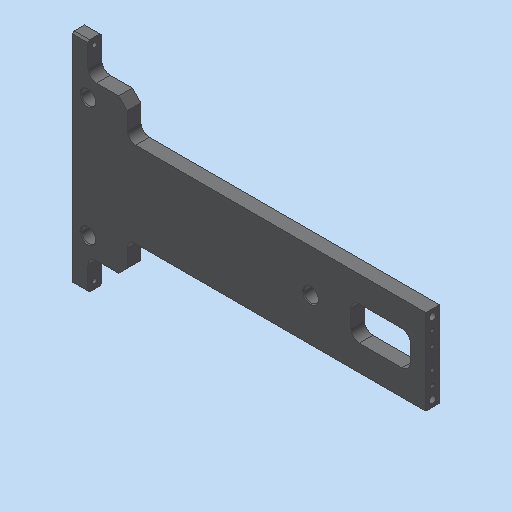
# Autodesk Inventor part: MM0861AN100_G01_120
Saved by Autodesk Inventor 2023.3 (Build 273359000, 359)
## iProperties
Created: 2018-10-29
Part Number: MM0861AN100_G01_120
Material: 1.2842 90MnCrV8
Document SubType Name: Modeling
Designer: Rose
Density: 7.85 g/cm^3
Appearance: Stahl - normal AnP
Mass: 675.833 g
Surface Area: 307.227 cm^2
Volume: 86.0934 cm^3
Description: =<RBPARTNOTITLE2>
RBMATERIAL: =<Material>
RBMATNO: =<Part Number>
RBPARTMADEOF: 150x8x210
RBPARTNOTITLE1: manufactured part
RBPARTNOTITLE2: Anfertigungsteil
MaxAbmaße: 0 x 0 x 0 (FM)
AnP_Material_aktuell: =<Material>
AnP_Kommentar_aktuell: =<Comments>
RBDRAWINGMISSINGSPEC: --
AnP_Kategorie: 1
AnP_Material: =<Material>
RBSURFACE2: HRC 58±2 cehm. vernickelt
Author: Rose
Keywords: =<RBPARTMADEOF>
Comments: =<RBSURFACE2>
Revision Number: 01
Autodesk Inventor part; units mm, degrees
ref_plane "YZ Plane" through (0, 0, 0) normal (1, 0, 0) x (0, 1, 0)
ref_plane "XZ Plane" through (0, 0, 0) normal (0, 1, 0) x (-1, 0, 0)
ref_plane "XY Plane" through (0, 0, 0) normal (0, 0, 1) x (1, 0, 0)
sketch "Skizze1" plane through (0, 0, 0) normal (0, 0, 1) x (1, 0, 0)
  line L0 (0, 9.6) -> (0, -1.6) projected
  line L1 (-41.4, 0) -> (248.4, 0) projected
  line L2 (0, 0) -> (207, 0)
  line L3 (207, 0) -> (207, 8)
  line L4 (207, 8) -> (0, 8)
  line L5 (0, 0) -> (0, 8)
  dimension "d0" = 8
  dimension "d1" = 0
  dimension "d4" = 207
  constraints: 8 end point, 2 perpendicular, 1 collinear, 1 point on line
  measures "d0" distance between parallel lines of L2 L4
  measures "d1" distance between parallel lines of L5 L0
  measures "d4" distance between parallel lines of L3 L0
extrude "Extrusion1" add sketch "Skizze1" along normal mid plane 128
sketch "Skizze2" plane through (0, 0, 64) normal (0, -1, 0) x (1, 0, 0)
  line L0 (0, 25.6) -> (0, -153.6) projected
  line L1 (-41.4, -64) -> (248.4, -64) projected
  point P0 (9, -29)
  point P1 (9, -99)
  point P2 (139.5, -64)
  dimension "d9" = 70
  dimension "d56" = 9
  dimension "d60" = 139.5
  constraints: 1 point on line, 1 symmetric about line
  measures "d9" distance of point (9, -99) point (9, -29)
  measures "d56" distance from line of point (9, -29) L0
  measures "d60" distance from line of point (139.5, -64) L0
hole "Bohrung1" at (9, 0, 35) at (9, 0, -35) at (139.5, 0, 0) direction (0, 1, 0) diameter 8.4 end through all
sketch "Skizze3" plane through (0, 8, 64) normal (0, 1, 0) x (1, 0, 0)
  line L0 (207, 0) -> (207, 128) projected
  line L1 (248.4, 64) -> (-41.4, 64) projected
  line L2 (9, 128) -> (9, 114)
  line L3 (14, 109) -> (32, 109)
  line L4 (9, 0) -> (9, 14)
  line L5 (14, 19) -> (32, 19)
  arc A0 (9, 114) -> (14, 109) centre (14, 114) ccw
  arc A1 (14, 19) -> (9, 14) centre (14, 14) ccw
  line L6 (168, 74) -> (193, 74)
  line L7 (193, 54) -> (168, 54)
  line L8 (163, 59) -> (163, 69)
  arc A2 (168, 74) -> (163, 69) centre (168, 69) ccw
  arc A3 (163, 59) -> (168, 54) centre (168, 59) ccw
  line L9 (0, 0) -> (0, 128) projected
  line L10 (0, 128) -> (207, 128) projected
  line L11 (207, 0) -> (0, 0) projected
  line L12 (37, 89) -> (207, 89)
  line L13 (37, 39) -> (207, 39)
  line L14 (32, 109) -> (32, 94)
  line L15 (32, 34) -> (32, 19)
  arc A4 (32, 94) -> (37, 89) centre (37, 94) ccw
  arc A5 (37, 39) -> (32, 34) centre (37, 34) ccw
  line L16 (198, 69) -> (198, 59)
  arc A6 (198, 69) -> (193, 74) centre (193, 69) ccw
  arc A7 (193, 54) -> (198, 59) centre (193, 59) ccw
  dimension "d22" = 5
  dimension "d23" = 90
  dimension "d25" = 5
  dimension "d28" = 20
  dimension "d52" = 50
  dimension "d53" = 44
  dimension "d54" = 9
  dimension "d55" = 32
  dimension "d61" = 9
  constraints: 24 end point, 16 point on circle, 16 tangent, 9 perpendicular, 8 centre point, 6 equal radius, 4 point on line, 1 collinear, 1 horizontal, 1 parallel, 1 symmetric about line, 2 other
  measures "d22" radius of A0
  measures "d23" distance between parallel lines of L5 L3
  measures "d25" radius of A2
  measures "d28" distance between parallel lines of L7 L6
  measures "d52" distance between parallel lines of L13 L12
  measures "d53" distance between parallel lines of L0 L8
  measures "d54" distance between parallel lines of L2 L9
  measures "d55" distance between parallel lines of L14 L9
  measures "d61" distance between parallel lines of L0 L16
extrude "Extrusion2" cut sketch "Skizze3" against normal through all contours L11 L4 A1 L5 L15 A5 L13 L0 | L12 A4 L14 L3 A0 L2 L10 L0 | L16 A7 L7 A3 L8 L1 | L1 L8 A2 L6 A6 L16
sketch "Skizze4" plane through (14, 8, 45) normal (0, 1, 0) x (1, 0, 0)
  line L0 (-14, 134.6) -> (-14, -44.6) projected
  line L1 (234.4, 45) -> (-55.4, 45) projected
  line L2 (149, 40) -> (149, 50) projected
  point P0 (8, 80)
  point P1 (8, 10)
  point P2 (140.5, 45)
  dimension "d38" = 22
  dimension "d39" = 70
  dimension "d97" = 8.5
  constraints: 1 point on line, 1 symmetric about line
  measures "d38" distance from line of L0 point (8, 80)
  measures "d39" distance of point (8, 10) point (8, 80)
  measures "d97" distance from line of point (140.5, 45) L2
hole "Bohrung2" at (22, 8, -35) at (22, 8, 35) at (154.5, 8, 0) direction (0, -1, 0) diameter 11.7 depth 6
sketch "Skizze5" plane through (0, 0, 64) normal (-1, 0, 0) x (0, 0, 1)
  line L0 (-153.6, 0) -> (25.6, 0) projected
  line L1 (-64, 9.6) -> (-64, -1.6) projected
  line L2 (-124, 4) -> (-4, 4)
  point P0 (-45, 4)
  point P1 (-83, 4)
  point P2 (-106, 4)
  point P3 (-22, 4)
  point P4 (-64, 4)
  dimension "d62" = 4
  dimension "d63" = 120
  dimension "d80" = 38
  dimension "d98" = 84
  constraints: 3 point on line, 3 symmetric about line, 2 end point, 1 coincident, 1 midpoint, 1 parallel
  measures "d62" distance from line of L0 L2.start
  measures "d63" distance of point (-4, 4) L2.start
  measures "d80" distance of point (-83, 4) point (-45, 4)
  measures "d98" distance of point (-22, 4) point (-106, 4)
hole "Bohrung3" at (0, 4, -60) at (0, 4, 60) at (0, 4, 19) at (0, 4, -19) at (0, 4, -42) at (0, 4, 0) at (0, 4, 42) direction (1, 0, 0) diameter 2.459 depth 11 tip angle 118 thread size "M3x0.5" designation "M3" class "6H" standard "ISO Metric profile"
sketch "Skizze6" plane through (207, 0, -25) normal (1, 0, 0) x (0, 0, -1)
  line L0 (-114.6, 0) -> (64.6, 0) projected
  line L1 (-25, -1.6) -> (-25, 9.6) projected
  line L2 (-11, 4) -> (-19, 4)
  point P0 (-39, 4)
  point P1 (-31, 4)
  dimension "d71" = 4
  dimension "d72" = 28
  dimension "d99" = 12
  constraints: 2 end point, 2 symmetric about line, 1 coincident, 1 perpendicular
  measures "d71" distance from line of L0 point (-39, 4)
  measures "d72" distance of L2.start point (-39, 4)
  measures "d99" distance of point (-19, 4) point (-31, 4)
hole "Bohrung4" at (207, 4, 14) at (207, 4, -14) at (207, 4, -6) at (207, 4, 6) direction (-1, 0, 0) diameter 2.459 depth 11 tip angle 118 thread size "M3x0.5" designation "M3" class "6H" standard "ISO Metric profile"
sketch "Skizze7" plane through (0, 0, 64) normal (-1, 0, 0) x (0, 0, 1)
  line L0 (-64, 9.6) -> (-64, -1.6) projected
  circle A0 centre (-124, 4) radius 1.2295 projected
  line L1 (-124, 4) -> (-91, 4)
  point P0 (-37, 4)
  dimension "d81" = 54
  constraints: 2 end point, 1 coincident, 1 perpendicular, 1 symmetric about line
  measures "d81" distance of point (-37, 4) point (-91, 4)
hole "Bohrung5" at (0, 4, -27) at (0, 4, 27) direction (1, 0, 0) diameter 4 depth 7 tip angle 118
sketch "Skizze8" plane through (207, 0, -25) normal (1, 0, 0) x (0, 0, -1)
  line L0 (-25, -1.6) -> (-25, 9.6) projected
  circle A0 centre (-39, 4) radius 1.2295 projected
  line L1 (-39, 4) -> (-46, 4)
  point P0 (-4, 4)
  dimension "d89" = 42
  constraints: 2 end point, 1 coincident, 1 perpendicular, 1 symmetric about line
  measures "d89" distance of point (-4, 4) point (-46, 4)
hole "Bohrung6" at (207, 4, 21) at (207, 4, -21) direction (-1, 0, 0) diameter 4 depth 7 tip angle 118
chamfer "Fase1" distance 5 angle 45 2 edges at (32, 4, 45) (32, 4, -45)
chamfer "Fase2" distance 1 angle 45 4 edges at (4.5, 8, -64) (4.5, 0, -64) (4.5, 8, 64) (4.5, 0, 64)
chamfer "Fase5" distance 0.5 angle 45 6 edges at (22, 8, -40.85) (9, 0, -30.8) (9, 0, 39.2) (22, 8, 29.15) (154.5, 8, -5.85) (139.5, 0, 4.2)
